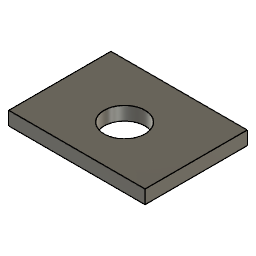
region_C (Autodesk Fusion 360 design; units mm, degrees)
Autodesk Fusion 360 part; units mm, degrees
sketch "Sketch1" plane through (0, 0, 0) normal (0, 0, 1) x (1, 0, 0)
  line L0 (-10, -10) -> (10, -10)
  line L1 (10, -10) -> (10, 10)
  line L2 (10, 10) -> (-10, 10)
  line L3 (-10, 10) -> (-10, -10)
  line L4 (-15, 5) -> (15, 5)
  circle A0 centre (0, -3) radius 3
extrude "Extrude1" add sketch "Sketch1" along normal blind 2 contours L0 L1 L3 L4
